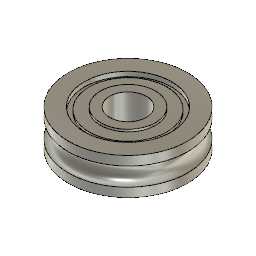
U604ZZ v3 (Autodesk Fusion 360 design; units mm, degrees)
Autodesk Fusion 360 part; units mm, degrees
sketch "Body" plane through (0, 0, 0) normal (0, 0, 1) x (1, 0, 0)
  circle A0 centre (0, 0) radius 2
  circle A1 centre (0, 0) radius 6.5
  circle A2 centre (0, 0) radius 3
  circle A3 centre (0, 0) radius 4.75
  circle A4 centre (0, 0) radius 4.25
  dimension "d1" = 4
  dimension "d2" = 13
  dimension "d3" = 6
  dimension "d4" = 9.5
  dimension "d5" = 8.5
  constraint coincident A0.centre A1.centre
  constraint concentric A0 A3
  constraint concentric A2 A4
  measures "d1" diameter of A0
  measures "d2" diameter of A1
  measures "d3" diameter of A2
  measures "d4" diameter of A3
  measures "d5" diameter of A4
extrude "Extrude1" add sketch "Body" along normal mid plane 4 contours A1 | A2 makes body 1 at (6.4919, -0.324, 1.3333) makes body 2 at (2.9963, -0.1495, 1.3333)
extrude "Extrude2" add sketch "Body" along normal mid plane 3.5 contours A4 bodies 2
extrude "Extrude3" add sketch "Body" along normal mid plane 3 contours A3 bodies 1 2
sketch "Sketch2" plane through (0, 0, 0) normal (1, 0, 0) x (0, 1, 0)
  line L0 (-6.5, -2) -> (6.5, -2)
  line L1 (6.5, 2) -> (-6.5, 2)
  line L2 (0, 2) -> (0, -2) construction
  line L3 (6.5, 2) -> (6.5, -2)
  line L4 (0, 0) -> (6.5, 0) construction
  circle A0 centre (6.5, 0) radius 1
  dimension "d12" = 2
  constraint midpoint L1 L2.start
  constraint midpoint L0 L2.end
  constraint coincident L1.start L3.start
  constraint coincident L0.end L3.end
  constraint coincident L4.start origin
  constraint midpoint L3 L4.end
  constraint coincident L4.end A0.centre
  measures "d12" diameter of A0
revolve "Revolve1" cut sketch "Sketch2" angle 360 about axis through (0, 0, 2) along (0, 0, -1) contours L3 A0 picked at (6.2733, -0.2444) bodies 1
